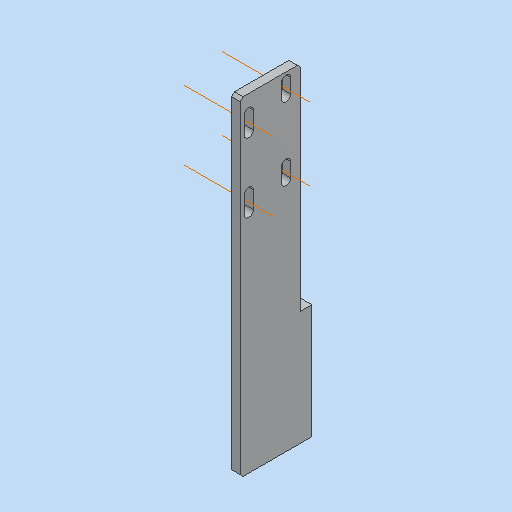
# Autodesk Inventor part: MM0948AN100_G01_116
Saved by Autodesk Inventor 2023.3 (Build 273359000, 359)
## iProperties
Part Number: MM0948AN100_G01_116
Material: 3.3206 AlMgSi0,5 - AW 6060
Description: =<RBPARTNOTITLE2>
Document SubType Name: Modeling
Designer: ric7an
Mass: 25.2568 g
Surface Area: 75.0692 cm^2
Volume: 9.35436 cm^3
Density: 2.7 g/cm^3
Appearance: Aluminium AnP
Vendor: --
Created: 2023-03-23
RBDOCUMENTTYPE: DRF
RBDOCUMENTVERSION: 00
RBDRAWINGMAINSCALE: 1:1
RBDRAWINGMISSINGSPEC: --
RBDRAWINGVOLUME: --
RBGBEDGESIN1: +0,5
RBGBEDGESIN2: +0,2
RBGBEDGESOUT1: -0,3
RBGBEDGESOUT2: -0,1
RBMATERIAL: =<Material>
RBMATMEETS: --
RBMATNO: =<Part Number>
RBPARTMADEOF: L 25 x 20 x 3 x115 (FM)
RBPARTNO: SIEHE MNR
RBPARTNOTITLE1: holder for sensor
RBPARTNOTITLE2: Sensorhalter
RBPARTSAFETYINDICATOR: --
RBSURFACE: anodised colourless
RBSURFACE2: eloxiert farblos
RBZEDGESNORM: ISO13715:2002-06
RBZGENDIMCLASS: m
RBZGENDIMNORM: ISO 2768-1:1989-11
RBZGENGEOCLASS: H
RBZGENGEONORM: ISO 2768-2:1989-11
RBZSURFACENORM: ISO13D2:2002-02
RBZTOLERANCENORM: ISO 14405-1:2010-12
AnP_Material: =<Material>
AnP_TemplVers: 20190222
AnP_Kategorie: 1
MaxAbmaße: 115 x 25 x 20 (FM)
AnP_Kommentar_aktuell: =<Comments>
AnP_Material_aktuell: =<Material>
Author: FH/Wi
Keywords: =<RBPARTMADEOF>
Comments: =<RBSURFACE2>
Revision Number: 01
Autodesk Inventor part; units mm, degrees
ref_plane "YZ Plane" through (0, 0, 0) normal (1, 0, 0) x (0, 1, 0)
ref_plane "XZ Plane" through (0, 0, 0) normal (0, 1, 0) x (-1, 0, 0)
ref_plane "XY Plane" through (0, 0, 0) normal (0, 0, 1) x (1, 0, 0)
sketch "Skizze1" plane through (0, 0, 0) normal (0, 0, 1) x (1, 0, 0)
  line L0 (0, 0) -> (20, 0)
  line L1 (20, 0) -> (20, 25)
  line L2 (20, 25) -> (0, 25)
  line L3 (0, 25) -> (0, 0)
  line L4 (0, 0) -> (17, 0)
  line L5 (17, 0) -> (17, 22)
  line L6 (17, 22) -> (0, 22)
  line L7 (0, 22) -> (0, 0)
  dimension "d0" = 20
  dimension "d1" = 25
  dimension "d2" = 3
  dimension "d3" = 3
  constraints: 16 end point, 4 parallel, 2 horizontal, 2 perpendicular
  measures "d0" distance of L1.end L2.end
  measures "d1" distance of L0.end L1.end
  measures "d2" distance between parallel lines of L2 L6
  measures "d3" distance between parallel lines of L1 L5
extrude "Extrusion1" add sketch "Skizze1" along normal blind 115 contours L5 L6 L3 L2 L1 L0
sketch "Skizze2" plane through (0, 25, 0) normal (0, 1, 0) x (1, 0, 0)
  line L0 (20, 0) -> (0, 0) projected
  line L1 (0, 0) -> (0, -115) projected
  line L2 (20, -115) -> (0, -115) projected
  line L3 (20, 0) -> (20, -115) projected
  line L4 (0, 0) -> (20, 0)
  line L5 (20, 0) -> (20, -40)
  line L6 (20, -40) -> (0, -40)
  line L7 (0, -40) -> (0, 0)
  point P0 (0, 0)
  dimension "d6" = 40
  constraints: 8 end point, 2 parallel, 1 horizontal, 1 perpendicular, 1 point on line
  measures "d6" distance between parallel lines of L0 L6
extrude "Extrusion2" cut sketch "Skizze2" against normal blind 4 contours L3 L2 L1 L6
chamfer "Fase1" distance 1 angle 45 5 edges at (18.5, 0, 115) (18.5, 21, 115) (0, 23.5, 40) (0, 23.5, 0) (18.5, 0, 0)
sketch "Skizze5" plane through (17, 21, 40) normal (-1, 0, 0) x (0, 0, 1)
  line L0 (39, -18) -> (45, -18) construction
  line L1 (39, -19.6) -> (45, -19.6)
  line L2 (45, -16.4) -> (39, -16.4)
  arc A0 (39, -16.4) -> (39, -19.6) centre (39, -18) ccw
  arc A1 (45, -19.6) -> (45, -16.4) centre (45, -18) ccw
  line L3 (63.15, -18) -> (69.15, -18) construction
  line L4 (63.15, -19.6) -> (69.15, -19.6)
  line L5 (69.15, -16.4) -> (63.15, -16.4)
  arc A2 (63.15, -16.4) -> (63.15, -19.6) centre (63.15, -18) ccw
  arc A3 (69.15, -19.6) -> (69.15, -16.4) centre (69.15, -18) ccw
  line L6 (74, -21) -> (-39, -21) projected
  line L7 (75, -1) -> (75, -20) projected
  line L8 (-40, -20) -> (-40, 1) projected
  line L9 (42.1, -5) -> (47.1, -5) construction
  line L10 (42.1, -6.6) -> (47.1, -6.6)
  line L11 (47.1, -3.4) -> (42.1, -3.4)
  arc A4 (42.1, -3.4) -> (42.1, -6.6) centre (42.1, -5) ccw
  arc A5 (47.1, -6.6) -> (47.1, -3.4) centre (47.1, -5) ccw
  line L12 (67.5, -5) -> (72.5, -5) construction
  line L13 (67.5, -3.4) -> (72.5, -3.4)
  line L14 (72.5, -6.6) -> (67.5, -6.6)
  arc A6 (67.5, -3.4) -> (67.5, -6.6) centre (67.5, -5) ccw
  arc A7 (72.5, -6.6) -> (72.5, -3.4) centre (72.5, -5) ccw
  point P0 (-40, -21)
  point P1 (42, -18)
  point P2 (66.15, -18)
  point P3 (44.6, -5)
  point P4 (70, -5)
  dimension "d31" = 3
  dimension "d32" = 3.2
  dimension "d33" = 6
  dimension "d34" = 6
  dimension "d35" = 24.15
  dimension "d37" = 82
  dimension "d50" = 3.2
  dimension "d51" = 3.2
  dimension "d52" = 5
  dimension "d53" = 5
  dimension "d54" = 25.4
  dimension "d56" = 110
  dimension "d57" = 13
  constraints: 32 end point, 16 point on circle, 16 tangent, 8 centre point, 5 parallel, 4 midpoint, 2 collinear, 2 horizontal, 2 point on line
  measures "d31" distance between parallel lines of L6 L3
  measures "d32" distance between parallel lines of L1 L2
  measures "d33" distance of L0.start L0.end
  measures "d34" distance of L3.start L3.end
  measures "d35" distance of point (66.15, -18) point (42, -18)
  measures "d37" distance from line of L8 point (42, -18)
  measures "d50" distance between parallel lines of L10 L11
  measures "d51" distance between parallel lines of L14 L13
  measures "d52" distance of L9.start L9.end
  measures "d53" distance of L12.start L12.end
  measures "d54" distance of point (70, -5) point (44.6, -5)
  measures "d56" distance from line of L8 point (70, -5)
  measures "d57" distance between parallel lines of L3 L12
extrude "Extrusion4" cut sketch "Skizze5" against normal through all
sketch "Skizze6" plane through (20, 25, 40) normal (0, 1, 0) x (1, 0, 0)
  line L0 (0, 40) -> (-19, 40) projected
  line L1 (-20, 39) -> (-20, 1) projected
  point P0 (-20, 40)
  point P1 (-11.5, 30)
  point P2 (-11.5, 10)
  dimension "d40" = 20
  dimension "d41" = 10
  dimension "d42" = 8.5
  constraints: 1 vertical alignment
  measures "d40" distance of point (-11.5, 10) point (-11.5, 30)
  measures "d41" distance from line of L0 point (-11.5, 30)
  measures "d42" distance from line of point (-11.5, 30) L1
hole "Bohrung2" at (8.5, 25, 10) at (8.5, 25, 30) direction (0, -1, 0) diameter 4.5 end through all clearance for "Inbusschraube ISO 4762  versenkt" size "M4" standard "ISO"
equation "\"d3\" = d2"
equation "\"d34\" = d33"
equation "\"d51\" = d50"
equation "\"d53\" = d52"
